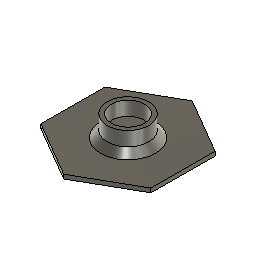
LAMP TWISTED TOP (Autodesk Fusion 360 design; units mm, degrees)
part number: 2026-05-21-08-55-42-044
Autodesk Fusion 360 part; units mm, degrees
sketch "Sketch1" plane through (0, 0, 0) normal (0, 0, 1) x (1, 0, 0)
  line L0 (33.3191, -19.4816) -> (33.5311, 19.1144)
  line L1 (33.5311, 19.1144) -> (0.212, 38.596)
  line L2 (0.212, 38.596) -> (-33.3191, 19.4816)
  line L3 (-33.3191, 19.4816) -> (-33.5311, -19.1144)
  line L4 (-33.5311, -19.1144) -> (-0.212, -38.596)
  line L5 (-0.212, -38.596) -> (33.3191, -19.4816)
  dimension "d11" = 38.596
  measures "d11" vertical distance of L4.end origin
extrude "Extrude1" add sketch "Sketch1" along normal blind 2.5
sketch "Sketch2" plane through (0, 0, 2.5) normal (0, 0, 1) x (-1, 0, 0)
  line L0 (0.212, 38.596) -> (-33.3191, 19.4816)
  line L1 (-33.3191, 19.4816) -> (-33.5311, -19.1144)
  line L2 (-33.5311, -19.1144) -> (-0.212, -38.596)
  line L3 (-0.212, -38.596) -> (33.3191, -19.4816)
  line L4 (33.3191, -19.4816) -> (33.5311, 19.1144)
  line L5 (33.5311, 19.1144) -> (0.212, 38.596)
  circle A0 centre (0, 0) radius 16.5
  dimension "d4" = 33
  constraint coincident A0.centre origin
  measures "d4" diameter of A0
extrude "Extrude2" add sketch "Sketch2" along normal blind 4 draft -45 contours A0
sketch "Sketch3" plane through (0, 0, 6.5) normal (0, 0, 1) x (-1, 0, 0)
  circle A0 centre (0, 0) radius 12.5
  circle A1 centre (0, 0) radius 12.5
  circle A2 centre (0, 0) radius 10
  dimension "d7" = 25
  dimension "d8" = 20
  constraint coincident A0.centre A1.centre
  constraint concentric A1 A2
  measures "d7" diameter of A1
  measures "d8" diameter of A2
extrude "Extrude3" add sketch "Sketch3" along normal blind 8.5
